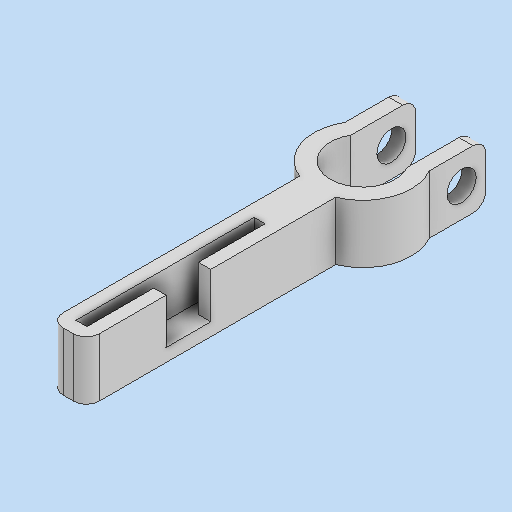
# Autodesk Inventor part: 2_12_bras_truc_tuyauv2
Saved by Autodesk Inventor 2026 (Build 300175050, 175E)
## iProperties
Created: 2025-06-22
Part Number: 2_12_bras_truc_tuyauv2
Material: Générique
Document SubType Name: Modeling
Designer: Diogo
Density: 1 g/cm^3
Appearance: Par défaut
Author: Diogo
Autodesk Inventor part; units mm, degrees
ref_plane "YZ Plane" through (0, 0, 0) normal (1, 0, 0) x (0, 1, 0)
ref_plane "XZ Plane" through (0, 0, 0) normal (0, 1, 0) x (-1, 0, 0)
ref_plane "XY Plane" through (0, 0, 0) normal (0, 0, 1) x (1, 0, 0)
sketch "Esquisse1" plane through (0, 0, 0) normal (0, 1, 0) x (-1, 0, 0)
  line L0 (0, 0) -> (-5.6, 0)
  line L1 (0, -38.5) -> (0, 0)
  arc A0 (1.5301, -47.9577) -> (-7.1301, -47.9577) centre (-2.8, -45.4577) ccw
  line L2 (-2.8, -45.4577) -> (8.9649, -52.2502) construction
  line L3 (-2.8, 8.9121) -> (-2.8, -74.6187) construction
  line L4 (1.5301, -47.9577) -> (1.5301, -57.9577)
  line L5 (3.6952, -49.2077) -> (3.6952, -57.9577)
  line L6 (3.6952, -57.9577) -> (1.5301, -57.9577)
  line L7 (-2.8, -45.4577) -> (-14.5649, -52.2502) construction
  line L8 (-7.1301, -47.9577) -> (-7.1301, -57.9577)
  line L9 (-9.2952, -49.2077) -> (-9.2952, -57.9577)
  line L10 (-9.2952, -57.9577) -> (-7.1301, -57.9577)
  arc A1 (-5.6, -38.5) -> (-9.2952, -49.2077) centre (-2.8, -45.4577) ccw
  arc A2 (3.6952, -49.2077) -> (0, -38.5) centre (-2.8, -45.4577) ccw
  line L11 (-5.6, 0) -> (-5.6, -38.5)
  point P0 (-2.8, -40.4577)
  dimension "d0" = 5.6
  dimension "d10" = 10
  dimension "d12" = 60
  dimension "d13" = 10
  dimension "d14" = 38.5
  constraints: 24 end point, 7 point on circle, 5 symmetric about line, 4 point on line, 4 vertical, 3 centre point, 1 coincident, 1 horizontal, 1 parallel, 1 perpendicular
  measures "d0" distance of L0.start L0.end
  measures "d10" diameter of A0
  measures "d12" angle of L3 L2
  measures "d13" distance of L4.start L4.end
  measures "d14" distance of L1.start L0.start
extrude "Extrusion1" add sketch "Esquisse1" along normal blind 9
sketch "Esquisse2" plane through (0, 9, 0) normal (0, 1, 0) x (1, 0, 0)
  line L0 (0, 0) -> (5.6, 0) projected
  line L1 (5.6, 0) -> (5.6, 38.5) projected
  line L2 (5.6, 12.3) -> (3.7, 12.3)
  line L3 (3.7, 12.3) -> (3.7, 2)
  line L4 (3.7, 2) -> (2, 2)
  line L5 (2, 2) -> (2, 29.5)
  line L6 (2, 29.5) -> (3.7, 29.5)
  line L7 (3.7, 29.5) -> (3.7, 19.2)
  line L8 (3.7, 19.2) -> (5.6, 19.2)
  line L9 (5.6, 19.2) -> (5.6, 12.3)
  dimension "d18" = 12.3
  dimension "d19" = 1.9
  dimension "d21" = 10.3
  dimension "d22" = 1.7
  dimension "d23" = 27.5
  dimension "d24" = 1.7
  dimension "d25" = 10.3
  constraints: 16 end point, 6 perpendicular, 4 point on line
  measures "d18" distance of L0.end L2.start
  measures "d19" distance of L2.start L2.end
  measures "d21" distance of L2.end L3.end
  measures "d22" distance of L3.end L4.end
  measures "d23" distance of L4.end L5.end
  measures "d24" distance of L5.end L6.end
  measures "d25" distance of L6.end L7.end
extrude "Extrusion2" cut sketch "Esquisse2" against normal blind 7
sketch "Esquisse3" plane through (9.2952, 0, -49.2077) normal (1, 0, 0) x (0, 0, -1)
  line L0 (-1.25, 9) -> (8.75, 9) construction
  line L1 (-1.25, 0) -> (8.75, 0) construction
  line L2 (8.75, 9) -> (8.75, 0) construction
  circle A0 centre (5, 4.5) radius 2.25
  line L3 (0, 0) -> (0, 9) construction
  point P0 (-49.2077, 0)
  point P1 (0, 4.5)
  dimension "d28" = 4.5
  dimension "d29" = 5
  constraints: 2 end point, 1 centre point, 1 midpoint, 1 vertical
  measures "d28" diameter of A0
  measures "d29" distance of point (0, 4.5) A0.centre
extrude "Extrusion3" cut sketch "Esquisse3" against normal through all
fillet "Congé1" radius 2 6 edges at (8.2127, 0, -57.9577) (8.2127, 9, -57.9577) (-2.6127, 9, -57.9577) (-2.6127, 0, -57.9577) (5.6, 4.5, 0) (0, 4.5, 0)
